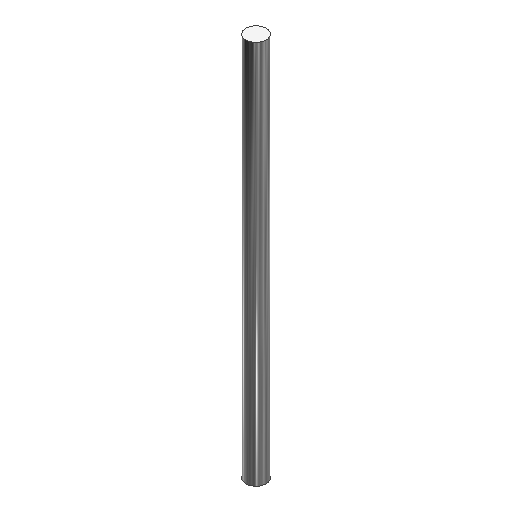
# Autodesk Inventor part: BUY - steel rod - 4 h8 x 75 - OT2-Pipette V0.6 placeholder
Saved by Autodesk Inventor 2025.5 (Build 295498000, 498)
## iProperties
Created: 2026-11-20
Part Number: BUY - steel rod - 4 h8 x 75 - OT2-Pipette V0.6 placeholder
Material: Generisch
Description: guide rod placeholder: 4 mm steel rod h8 x 75 (silver steel or a ground shaft), eject variant
Document SubType Name: Modeling
Designer: benir
Density: 1 g/cm^3
Appearance: Chrome - Polished
Author: benir
Autodesk Inventor part; units mm, degrees
ref_plane "YZ Plane" through (0, 0, 0) normal (1, 0, 0) x (0, 1, 0)
ref_plane "XY Plane" through (0, 0, 0) normal (0, 0, 1) x (1, 0, 0)
ref_plane "y=rod_y0" through (0, 48, 0) normal (0, 1, 0) x (-1, 0, 0)
sketch "rod" plane through (0, 48, 0) normal (0, 1, 0) x (-1, 0, 0)
  circle A0 centre (-18.5, -22) radius 2
  point P0 (0, 0)
  dimension "d3" = 22
  dimension "d4" = 18.5
  dimension "d5" = 4
  constraints: 1 centre point
  measures "d3" vertical distance of point (0, 0) A0.centre
  measures "d4" horizontal distance of point (0, 0) A0.centre
  measures "d5" diameter of A0
extrude "4 mm steel rod" add sketch "rod" along normal blind 75
equation "\"d3\" = -rod_z"
equation "\"d4\" = rod_x"
equation "\"d5\" = rod_d"
equation "\"d6\" = rod_len"
equation "\"rod_d\" = 4"
equation "\"rod_len\" = 75"
equation "\"rod_z\" = -22"
equation "\"rod_x\" = 18.5"
body "Solid2"
